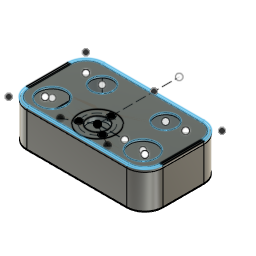
Arcade spinner v4 (Autodesk Fusion 360 design; units mm, degrees)
Autodesk Fusion 360 part; units mm, degrees
sketch "Sketch1" plane through (0, 0, 0) normal (0, 0, 1) x (1, 0, 0)
  circle A0 centre (-50, 0) radius 15
  circle A1 centre (50, 0) radius 15
  circle A2 centre (0, 0) radius 11
  circle A3 centre (0, 0) radius 20
  line L0 (-55, 62.1698) -> (55, 62.1698)
  line L1 (75, 42.1698) -> (75, -2.8302)
  line L2 (55, -22.8302) -> (-55, -22.8302)
  line L3 (-75, -2.8302) -> (-75, 42.1698)
  arc A4 (-55, 62.1698) -> (-75, 42.1698) centre (-55, 42.1698) ccw
  arc A5 (75, 42.1698) -> (55, 62.1698) centre (55, 42.1698) ccw
  arc A6 (55, -22.8302) -> (75, -2.8302) centre (55, -2.8302) ccw
  arc A7 (-75, -2.8302) -> (-55, -22.8302) centre (-55, -2.8302) ccw
  circle A8 centre (-35, 40) radius 12
  circle A9 centre (35, 40) radius 12
  line L4 (-73, -2.8302) -> (-73, 42.1698)
  arc A10 (-55, 60.1698) -> (-73, 42.1698) centre (-55, 42.1698) ccw
  line L5 (-55, 60.1698) -> (55, 60.1698)
  arc A11 (73, 42.1698) -> (55, 60.1698) centre (55, 42.1698) ccw
  line L6 (73, 42.1698) -> (73, -2.8302)
  arc A12 (55, -20.8302) -> (73, -2.8302) centre (55, -2.8302) ccw
  line L7 (55, -20.8302) -> (-55, -20.8302)
  arc A13 (-73, -2.8302) -> (-55, -20.8302) centre (-55, -2.8302) ccw
  line L8 (0, 0) -> (0, 90) construction
  circle A14 centre (0, 0) radius 15 construction
  line L9 (0, 0) -> (25.9808, -15) construction
  line L10 (0, 0) -> (30, 0) construction
  line L11 (0, 0) -> (-25.9808, -15) construction
  line L12 (0, 0) -> (30, 0) construction
  arc A15 (72, 42.1698) -> (55, 59.1698) centre (55, 42.1698) ccw
  line L13 (-55, 59.1698) -> (55, 59.1698)
  arc A16 (-55, 59.1698) -> (-72, 42.1698) centre (-55, 42.1698) ccw
  line L14 (-72, -2.8302) -> (-72, 42.1698)
  arc A17 (-72, -2.8302) -> (-55, -19.8302) centre (-55, -2.8302) ccw
  line L15 (55, -19.8302) -> (-55, -19.8302)
  arc A18 (55, -19.8302) -> (72, -2.8302) centre (55, -2.8302) ccw
  line L16 (72, 42.1698) -> (72, -2.8302)
  point P0 (-75, 62.1698)
  point P1 (75, 62.1698)
  point P2 (-75, -22.8302)
  point P3 (0, 15)
  point P4 (-12.9904, -7.5)
  point P5 (12.9904, -7.5)
  point P6 (0, 62.1698)
  dimension "d1" = 30
  dimension "d2" = 30
  dimension "d3" = 22
  dimension "d4" = 40
  dimension "d5" = 150
  dimension "d6" = 85
  dimension "d8" = 20
  dimension "d9" = 24
  dimension "d10" = 24
  dimension "d11" = -2
  dimension "d16" = 30
  dimension "d17" = 30
  dimension "d18" = 30
  dimension "d19" = 150
  dimension "d20" = 30
  dimension "d62" = 3
  constraint coincident A2.centre A3.centre
  constraint horizontal L0
  constraint perpendicular L0 L1
  constraint perpendicular L1 L2
  constraint perpendicular L2 L3
  constraint coincident P0 L0
  constraint coincident P0 L3
  constraint tangent L0 A4
  constraint tangent L3 A4
  constraint coincident P1 L0
  constraint coincident P1 L1
  constraint tangent L0 A5
  constraint tangent L1 A5
  constraint equal A4 A5
  constraint tangent L1 A6
  constraint tangent L2 A6
  constraint equal A4 A6
  constraint coincident P2 L2
  constraint coincident P2 L3
  constraint tangent L2 A7
  constraint tangent L3 A7
  constraint equal A4 A7
  constraint vertical L8
  constraint horizontal L10
  constraint horizontal L12
  constraint midpoint L11 P4
  constraint midpoint L9 P5
  constraint coincident A14 P3
  constraint coincident L8 P3
  constraint midpoint L0 P6
  constraint coincident L8 P6
  measures "d1" diameter of A0
  measures "d2" diameter of A1
  measures "d3" diameter of A2
  measures "d4" diameter of A3
  measures "d5" distance of P0 P1
  measures "d6" distance of P0 P2
  measures "d8" radius of A4
  measures "d9" diameter of A8
  measures "d10" diameter of A9
  measures "d16" diameter of A14
  measures "d17" distance of A2.centre L9.end
  measures "d18" angle of L9 L10
  measures "d19" angle of L11 L12
  measures "d20" distance of A2.centre L11.end
extrude "Extrude1" add sketch "Sketch1" against normal blind 2 contours A3 L15 | A3 A15 L13 A16 L14 A17 L15 A18 L16 | A3 L15 | L0 L1 L2 L3 A4 A5 A6 A7 | L4 A10 L5 A11 L6 A12 L7 A13 makes body 1
extrude "Extrude3" add sketch "Sketch1" against normal blind 5 contours A3 L15 | A3 L15 bodies 1
hole "Hole1" at (-12.9904, -7.5, 0) at (0, 15, 0) at (12.9904, -7.5, 0) direction (0, 0, -1) diameter 4 depth 8 tip angle 180 counterbore diameter 8 counterbore depth 2 bodies 1
extrude "Extrude4" add sketch "Sketch1" against normal blind 40 contours L0 L1 L2 L3 A4 A5 A6 A7 bodies 1
sketch "Sketch2" plane through (0, 62.1698, 0) normal (0, 1, 0) x (-1, 0, 0)
  line L0 (55, 0) -> (-55, 0)
  line L1 (-55, 0) -> (-55, -40)
  line L2 (-55, -40) -> (55, -40)
  line L3 (55, -40) -> (55, 0)
  line L4 (-5, -3.5) -> (5, -3.5)
  line L5 (5, -3.5) -> (5, -6.9)
  line L6 (5, -6.9) -> (-5, -6.9)
  line L7 (-5, -6.9) -> (-5, -3.5)
  line L8 (0, 0) -> (0, -16.0078) construction
  line L9 (55, 0) -> (-55, 0) construction
  line L10 (11, -2) -> (-11, -2)
  line L11 (-11, -2) -> (-11, -4)
  line L12 (-11, -4) -> (11, -4)
  line L13 (11, -4) -> (11, -2)
  line L14 (-55, 0) -> (55, 0)
  dimension "d39" = 10
  dimension "d40" = 3.4
  dimension "d41" = 5
  dimension "d42" = 3.5
  dimension "d45" = 22
  dimension "d46" = 2
  dimension "d47" = 2
  dimension "d48" = 11
  constraint horizontal L4
  constraint vertical L5
  constraint horizontal L6
  constraint vertical L7
  constraint coincident L8.start origin
  constraint perpendicular L0 L8
  constraint horizontal L10
  constraint vertical L11
  constraint horizontal L12
  constraint vertical L13
  measures "d39" distance of L4.start L4.end
  measures "d40" distance of L4.start L6.end
  measures "d41" distance of L7 L8
  measures "d42" distance of L4 L9
  measures "d45" distance of L10.start L10.end
  measures "d46" distance of L10.start L12.end
  measures "d47" distance of L10 L14
  measures "d48" distance of L8 L13
extrude "Extrude6" cut sketch "Sketch2" against normal blind 9 contours L4 L5 L7 L12 | L5 L6 L7 L12 bodies 1
extrude "Extrude8" cut sketch "Sketch2" against normal blind 14 from surface at -1 contours L4 L5 L7 L10 L11 L12 L13 | L4 L5 L7 L12 bodies 1
fillet "Fillet4" radius 3 8 edges at (69.1421, 56.3119, 0) (75, 19.6698, 0) (69.1421, -16.9723, 0) (0, -22.8302, 0) (-69.1421, -16.9723, 0) (-75, 19.6698, 0) (-69.1421, 56.3119, 0) (0, 62.1698, 0) on bodies 1
extrude "Extrude9" add sketch "Sketch1" against normal blind 1 from surface at -40 separate body contours A0 | A1 | A2 | A3 L15 | A3 A15 L13 A16 L14 A17 L15 A18 L16 | A3 L15 | L0 L1 L2 L3 A4 A5 A6 A7 | A8 | A9 | L4 A10 L5 A11 L6 A12 L7 A13 makes body 2
extrude "Extrude10" add sketch "Sketch1" along normal blind 5 from surface at -40 contours L4 A10 L5 A11 L6 A12 L7 A13 bodies 2
